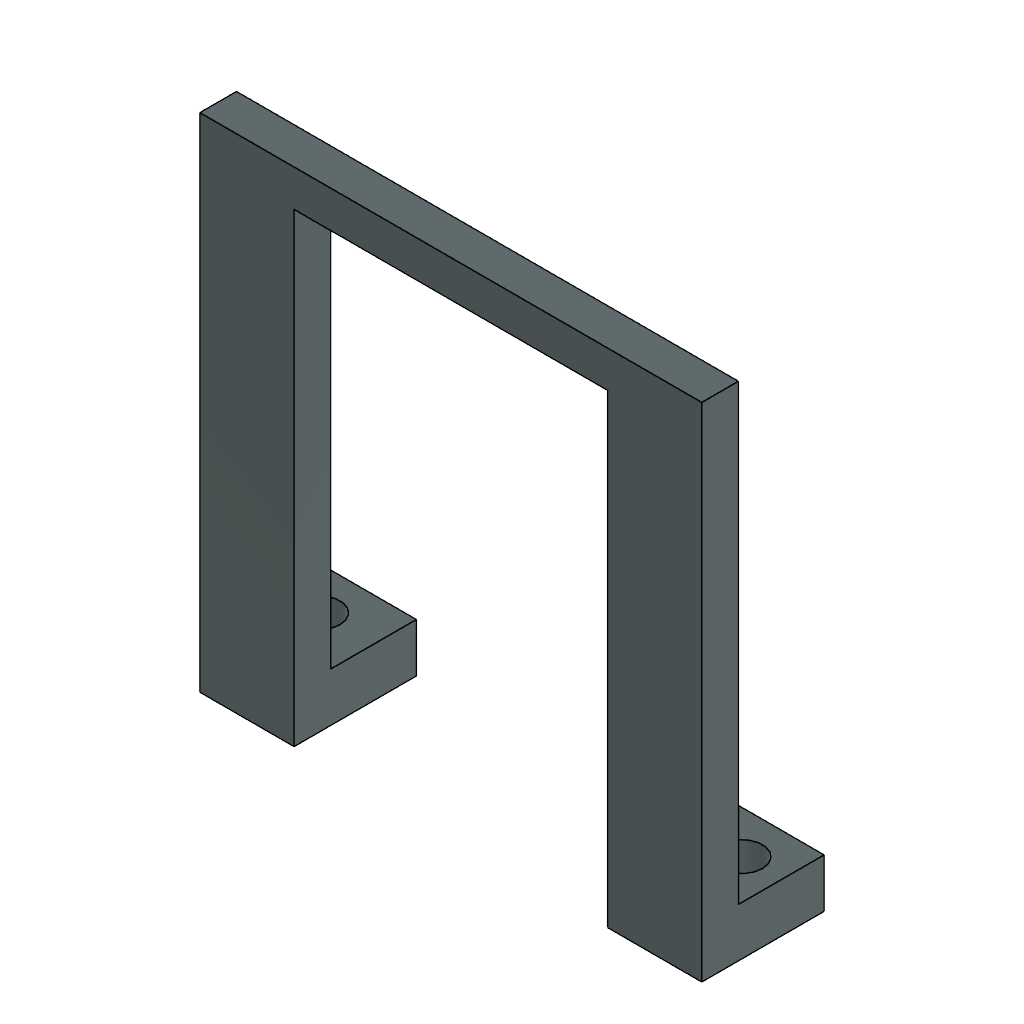
Scout-ESP32-CAM-Rear-Support-v1 (Autodesk Fusion 360 design; units mm, degrees)
Autodesk Fusion 360 part; units mm, degrees
ref_plane "WorkPlane1" through (0, 0, 32) normal (0, 0, 1) x (1, 0, 0)
sketch "Left slider foot profile" plane through (0, 0, 32) normal (0, 0, 1) x (1, 0, 0)
  line L0 (-20.5, -28) -> (-12.8, -28)
  line L1 (-12.8, -28) -> (-12.8, -18)
  line L2 (-12.8, -18) -> (-20.5, -18)
  line L3 (-20.5, -18) -> (-20.5, -28)
extrude "Left slider foot" add sketch "Left slider foot profile" along normal blind 4 makes body 1
ref_plane "WorkPlane2" through (0, 0, 36) normal (0, 0, 1) x (1, 0, 0)
sketch "Left rear PCB edge support profile" plane through (0, 0, 36) normal (0, 0, 1) x (1, 0, 0)
  line L0 (-20.5, -28) -> (-12.8, -28)
  line L1 (-12.8, -28) -> (-12.8, -25)
  line L2 (-12.8, -25) -> (-20.5, -25)
  line L3 (-20.5, -25) -> (-20.5, -28)
extrude "Left rear PCB edge support" add sketch "Left rear PCB edge support profile" along normal blind 37 separate body makes body 2
ref_plane "WorkPlane3" through (0, 0, 32) normal (0, 0, 1) x (1, 0, 0)
sketch "Right slider foot profile" plane through (0, 0, 32) normal (0, 0, 1) x (1, 0, 0)
  line L0 (12.8, -28) -> (20.5, -28)
  line L1 (20.5, -28) -> (20.5, -18)
  line L2 (20.5, -18) -> (12.8, -18)
  line L3 (12.8, -18) -> (12.8, -28)
extrude "Right slider foot" add sketch "Right slider foot profile" along normal blind 4 separate body makes body 3
ref_plane "WorkPlane4" through (0, 0, 36) normal (0, 0, 1) x (1, 0, 0)
sketch "Right rear PCB edge support profile" plane through (0, 0, 36) normal (0, 0, 1) x (1, 0, 0)
  line L0 (12.8, -28) -> (20.5, -28)
  line L1 (20.5, -28) -> (20.5, -25)
  line L2 (20.5, -25) -> (12.8, -25)
  line L3 (12.8, -25) -> (12.8, -28)
extrude "Right rear PCB edge support" add sketch "Right rear PCB edge support profile" along normal blind 37 separate body makes body 4
ref_plane "WorkPlane5" through (0, 0, 70) normal (0, 0, 1) x (1, 0, 0)
sketch "Rear support upper bridge profile" plane through (0, 0, 70) normal (0, 0, 1) x (1, 0, 0)
  line L0 (-20.5, -28) -> (20.5, -28)
  line L1 (20.5, -28) -> (20.5, -25)
  line L2 (20.5, -25) -> (-20.5, -25)
  line L3 (-20.5, -25) -> (-20.5, -28)
extrude "Rear support upper bridge" add sketch "Rear support upper bridge profile" along normal blind 3 separate body makes body 5
combine "Join rear support" operation add target body 1 tool bodies 2 3 4 5
ref_plane "WorkPlane6" through (0, 0, 31) normal (0, 0, 1) x (1, 0, 0)
sketch "Two M3 rear support clearance holes" plane through (0, 0, 31) normal (0, 0, 1) x (1, 0, 0)
  circle A0 centre (-17.25, -21.5) radius 1.7
  circle A1 centre (17.25, -21.5) radius 1.7
extrude "Rear support M3 bolt holes" cut sketch "Two M3 rear support clearance holes" along normal blind 7 bodies 1
named bodies: "Adjustable rear support - PRINT ONE", "Left rear PCB edge support", "Right slider foot", "Right rear PCB edge support", "Rear support upper bridge"
